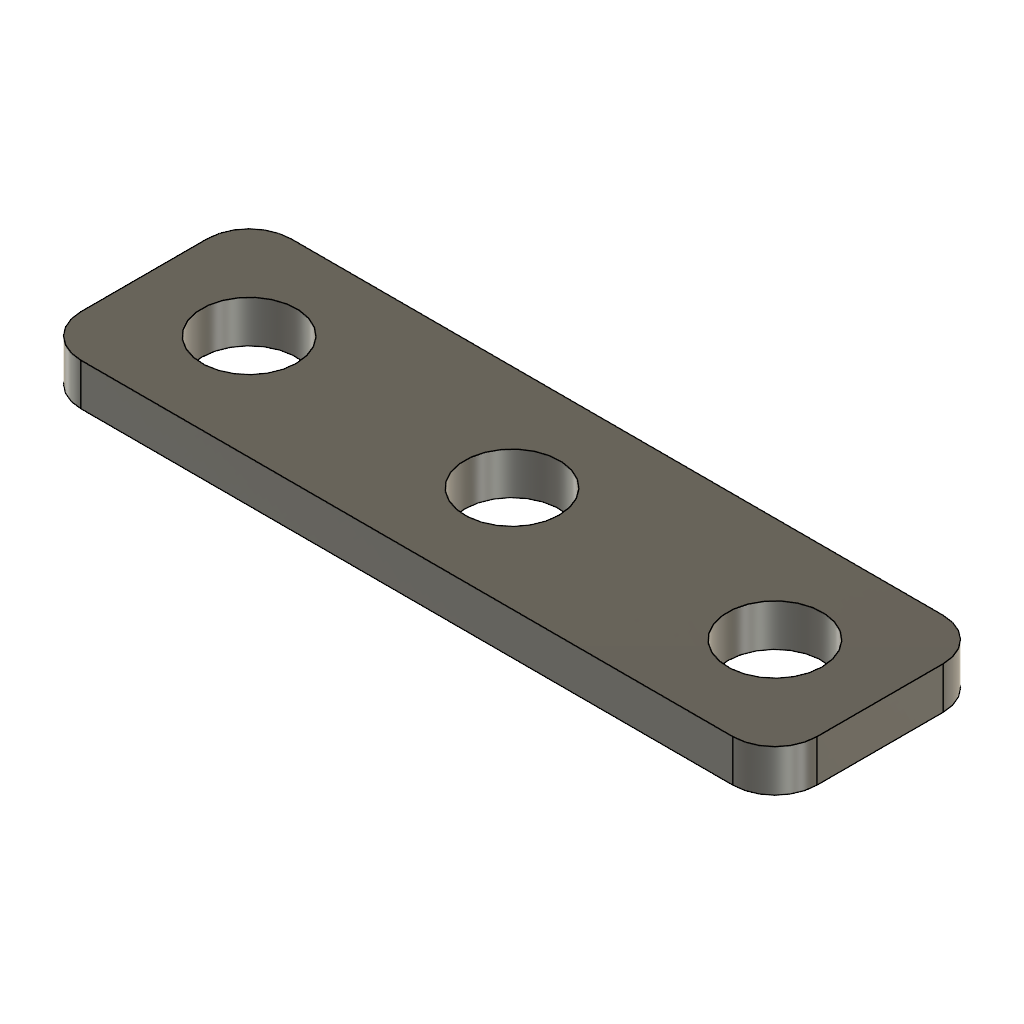
compression (Autodesk Fusion 360 design; units mm, degrees)
part number: 2026-08-28-11-17-18-521
Autodesk Fusion 360 part; units mm, degrees
sketch "Sketch1" plane through (0, 0, 0) normal (0, 0, 1) x (1, 0, 0)
  line L0 (-17.5, 5) -> (17.5, 5)
  line L1 (17.5, 5) -> (17.5, -5)
  line L2 (17.5, -5) -> (-17.5, -5)
  line L3 (-17.5, -5) -> (-17.5, 5)
  dimension "d1" = 10
  dimension "d2" = 35
  dimension "d3" = 17.5
  dimension "d4" = 5
  constraint horizontal L0
  constraint vertical L1
  constraint horizontal L2
  constraint vertical L3
  measures "d1" distance of L0 L2
  measures "d2" distance of L1 L3
  measures "d3" horizontal distance of origin L1.end
  measures "d4" vertical distance of origin L1.end
extrude "Extrude1" add sketch "Sketch1" along normal blind 2
sketch "Sketch2" plane through (0, 0, 2) normal (0, 0, 1) x (-1, 0, 0)
  line L0 (17.5, 5) -> (-17.5, 5)
  line L1 (-17.5, 5) -> (-17.5, -5)
  line L2 (-17.5, -5) -> (17.5, -5)
  line L3 (17.5, -5) -> (17.5, 5)
  point P0 (12.5, 0)
  point P1 (-12.5, 0)
  dimension "d7" = 12.5
  dimension "d8" = 12.5
  constraint horizontal origin P1
  constraint horizontal origin P0
  measures "d7" distance of origin P0
  measures "d8" distance of origin P1
hole "Hole1" at (-12.5, 0, 2) at (0, 0, 2) at (12.5, 0, 2) direction (0, 0, -1) diameter 4.5 end through all
fillet "Fillet1" radius 2 4 edges at (-17.5, -5, 1) (17.5, -5, 1) (17.5, 5, 1) (-17.5, 5, 1)
